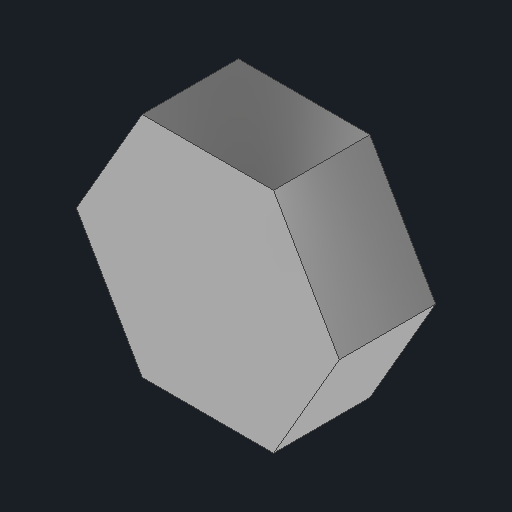
# Autodesk Inventor part: m8_bolt_head
Saved by Autodesk Inventor 2027.1 (Build 311270010, 270A)
## iProperties
Created: 2026-11-04
Part Number: m8_bolt_head
Material: Generic
Description: M8 hex bolt head (tripod leg hinge)
Document SubType Name: Modeling
Designer: Claude (from photos)
Density: 1 g/cm^3
Appearance: Stainless Steel - Bright
Author: alexg
Autodesk Inventor part; units mm, degrees
ref_plane "YZ Plane" through (0, 0, 0) normal (1, 0, 0) x (0, 1, 0)
ref_plane "XZ Plane" through (0, 0, 0) normal (0, 1, 0) x (-1, 0, 0)
ref_plane "XY Plane" through (0, 0, 0) normal (0, 0, 1) x (1, 0, 0)
sketch "Hex head 13 sketch" plane through (0, 0, 0) normal (0, 0, 1) x (1, 0, 0)
  line L0 (7.5056, 0) -> (3.7528, 6.5)
  line L1 (3.7528, 6.5) -> (-3.7528, 6.5)
  line L2 (-3.7528, 6.5) -> (-7.5056, 0)
  line L3 (-7.5056, 0) -> (-3.7528, -6.5)
  line L4 (-3.7528, -6.5) -> (3.7528, -6.5)
  line L5 (3.7528, -6.5) -> (7.5056, 0)
  constraints: 12 end point
extrude "Hex head 13" add sketch "Hex head 13 sketch" along normal blind 5.5
body "Solid1"
